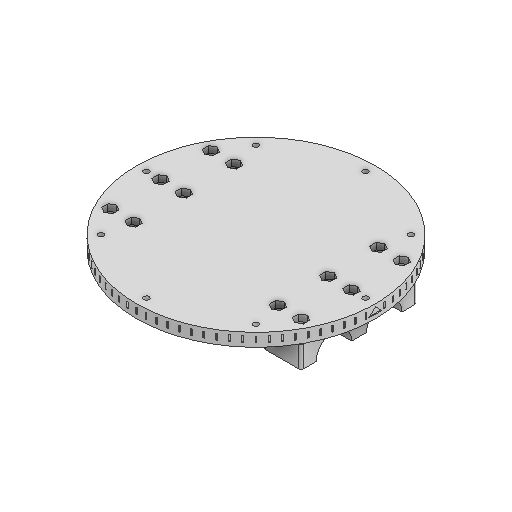
# Autodesk Inventor part: 3DP_PLA_A_Axis_Rotating_Stage_Fiberglass_pipes_mount_plate
Saved by Autodesk Inventor 2027 (Build 310192060, 192F)
## iProperties
Created: 2026-01-06
Part Number: 3DP_PLA_A_Axis_Rotating_Stage_Fiberglass_pipes_mount_plate
Material: Generic
Document SubType Name: Modeling
Designer: User
Density: 1 g/cm^3
Appearance: Default
Author: User
Autodesk Inventor part; units mm, degrees
ref_plane "XZ Plane" through (0, 0, 0) normal (0, 1, 0) x (-1, 0, 0)
ref_plane "XY Plane" through (0, 0, 0) normal (0, 0, 1) x (1, 0, 0)
sketch "Sketch1" plane through (0, 0, 0) normal (0, 1, 0) x (-1, 0, 0)
  circle A0 centre (0, 0) radius 92.675
  point P0 (85, 0)
  point P1 (60.1041, 60.1041)
  point P2 (0, 85)
  point P3 (-60.1041, 60.1041)
  point P4 (-85, 0)
  point P5 (-60.1041, -60.1041)
  point P6 (0, -85)
  point P7 (60.1041, -60.1041)
  dimension "d0" = 185.35
  dimension "d1" = 85
  dimension "d4" = 360
  constraints: 1 centre point, 1 coincident, 9 other
  measures "d0" diameter of A0
  measures "d1" distance of point (0, 0) point (85, 0)
extrude "Extrusion1" add sketch "Sketch1" along normal blind 10
hole "Hole1" at (-85, 0, 0) at (-60.1041, 0, 60.1041) at (0, 0, 85) at (60.1041, 0, 60.1041) at (85, 0, 0) at (60.1041, 0, -60.1041) at (0, 0, -85) at (-60.1041, 0, -60.1041) direction (0, 1, 0) diameter 4.2 end through all
sketch "Sketch3" plane through (0, 0, 0) normal (0, -1, 0) x (1, 0, 0)
  line L0 (-86.6006, 33) -> (86.6006, 33)
  line L1 (92.4806, 6) -> (-92.4806, 6)
  line L2 (-92.4806, -6) -> (92.4806, -6)
  line L3 (86.6006, -33) -> (-86.6006, -33)
  circle A0 centre (-60.1041, -60.1041) radius 2.1 projected
  circle A1 centre (0, -85) radius 2.1 projected
  circle A2 centre (60.1041, -60.1041) radius 2.1 projected
  circle A3 centre (85, 0) radius 2.1 projected
  circle A4 centre (60.1041, 60.1041) radius 2.1 projected
  circle A5 centre (0, 85) radius 2.1 projected
  circle A6 centre (-60.1041, 60.1041) radius 2.1 projected
  circle A7 centre (-85, 0) radius 2.1 projected
  circle A8 centre (0, 0) radius 92.675 projected
  line L4 (80, 45) -> (50, 45)
  line L5 (50, 45) -> (50, -45)
  line L6 (50, -45) -> (80, -45)
  line L7 (80, -45) -> (80, 45)
  line L8 (-50, 45) -> (-80, 45)
  line L9 (-80, 45) -> (-80, -45)
  line L10 (-80, -45) -> (-50, -45)
  line L11 (-50, -45) -> (-50, 45)
  line L12 (0, 85) -> (0, -85)
  point P0 (74, 39)
  point P1 (56, 39)
  point P2 (74, 0)
  point P3 (56, 0)
  point P4 (74, -39)
  point P5 (56, -39)
  point P6 (-74, 39)
  point P7 (-56, 39)
  point P8 (-74, 0)
  point P9 (-56, 0)
  point P10 (-74, -39)
  point P11 (-56, -39)
  dimension "d15" = 27
  dimension "d16" = 27
  dimension "d17" = 6
  dimension "d18" = 6
  dimension "d19" = 12
  dimension "d20" = 12
  dimension "d21" = 30
  dimension "d22" = 50
  dimension "d23" = 30
  dimension "d24" = 12
  dimension "d25" = 12
  dimension "d26" = 50
  dimension "d37" = 6
  dimension "d38" = 6
  dimension "d39" = 6
  dimension "d40" = 6
  dimension "d41" = 39
  dimension "d42" = 39
  dimension "d43" = 78
  constraints: 26 end point, 6 parallel, 6 symmetric about line, 4 horizontal, 4 vertical alignment, 2 horizontal alignment, 2 perpendicular, 1 vertical, 9 other
  measures "d15" distance between parallel lines of L0 L1
  measures "d16" distance between parallel lines of L3 L2
  measures "d17" distance from line of point (0, 0) L1
  measures "d18" distance from line of L2 point (0, 0)
  measures "d19" distance between parallel lines of L0 L4
  measures "d20" distance between parallel lines of L6 L3
  measures "d21" distance between parallel lines of L7 L5
  measures "d22" distance from line of point (0, 0) L5
  measures "d23" distance of L8.start L8.end
  measures "d24" distance between parallel lines of L0 L8
  measures "d25" distance between parallel lines of L3 L10
  measures "d26" distance from line of point (0, 0) L11
  measures "d37" distance from line of L4 point (56, 39)
  measures "d38" distance from line of L6 point (56, -39)
  measures "d39" distance from line of L5 point (56, 39)
  measures "d40" distance from line of L7 point (74, 39)
  measures "d41" distance of point (56, 0) point (56, 39)
  measures "d42" distance of point (74, 39) point (74, 0)
  measures "d43" distance of point (74, -39) point (74, 39)
extrude "Extrusion2" add sketch "Sketch3" along normal blind 18.5 contours L9 L8 L11 L0 | L0 L11 L1 L9 | L1 L11 L2 L9 | L7 L1 L5 L0 | L0 L5 L4 L7 | L2 L11 L3 L9 | L7 L2 L5 L1 | L3 L11 L10 L9 | L7 L3 L5 L2 | L7 L6 L5 L3
sketch "Sketch4" plane through (-80, 0, -45) normal (-1, 0, 0) x (0, 0, 1)
  line L0 (0, 0) -> (90, 0) projected
  line L1 (0, 0) -> (0, -18.5) projected
  line L2 (90, -18.5) -> (0, -18.5) projected
  line L3 (90, 0) -> (90, -18.5) projected
  circle A0 centre (64.5, -18.5) radius 13.75
  circle A1 centre (25.5, -18.5) radius 13.75
  line L4 (90, -18.5) -> (0, -18.5) projected
  point P0 (45, 0)
  point P1 (45, -18.5)
  point P2 (45, -18.5)
  dimension "d29" = 27.5
  dimension "d30" = 27.5
  dimension "d31" = 45
  dimension "d32" = 90
  dimension "d33" = 19.5
  dimension "d34" = 19.5
  constraints: 2 centre point, 2 midpoint, 2 point on line
  measures "d29" diameter of A0
  measures "d30" diameter of A1
  measures "d31" distance from line of L3 point (45, -18.5)
  measures "d32" distance between parallel lines of L1 L3
  measures "d33" distance of point (45, -18.5) A0.centre
  measures "d34" distance of point (45, -18.5) A1.centre
extrude "Extrusion3" cut sketch "Sketch4" against normal through all contours A1 L2 | L2 A1 | A0 L2 | L2 A0
hole "Hole2" at (74, 0, 39) at (56, 0, 39) at (74, 0, 0) at (56, 0, 0) at (74, 0, -39) at (56, 0, -39) at (-56, 0, 39) at (-56, 0, 0) at (-56, 0, -39) at (-74, 0, -39) at (-74, 0, 0) at (-74, 0, 39) direction (0, 1, 0) diameter 5.2 end through all both
fillet "Fillet1" radius 2 8 edges at (-80, -9.25, 45) (-50, -9.25, 45) (-80, -9.25, -45) (-50, -9.25, -45) (50, -9.25, 45) (80, -9.25, 45) (50, -9.25, -45) (80, -9.25, -45)
chamfer "Chamfer1" distance 2 angle 45 16 edges at (50, 0, 0) (50.5858, 0, 44.4142) (65, 0, 45) (79.4142, 0, 44.4142) (80, 0, 0) (79.4142, 0, -44.4142) (65, 0, -45) (50.5858, 0, -44.4142) (-65, 0, 45) (-50.5858, 0, 44.4142) (-50, 0, 0) (-50.5858, 0, -44.4142) (-65, 0, -45) (-79.4142, 0, -44.4142) (-80, 0, 0) (-79.4142, 0, 44.4142)
sketch "Sketch5" plane through (0, 10, 0) normal (0, 1, 0) x (1, 0, 0)
  circle A0 centre (-74, -39) radius 2.6 projected
  circle A1 centre (-74, 0) radius 2.6 projected
  circle A2 centre (-74, 39) radius 2.6 projected
  circle A3 centre (-56, 39) radius 2.6 projected
  circle A4 centre (-56, 0) radius 2.6 projected
  circle A5 centre (-56, -39) radius 2.6 projected
  circle A6 centre (56, 39) radius 2.6 projected
  circle A7 centre (74, 39) radius 2.6 projected
  circle A8 centre (56, 0) radius 2.6 projected
  circle A9 centre (74, 0) radius 2.6 projected
  circle A10 centre (56, -39) radius 2.6 projected
  circle A11 centre (74, -39) radius 2.6 projected
  circle A12 centre (-60.1041, 60.1041) radius 2.1 projected
  circle A13 centre (0, 85) radius 2.1 projected
  circle A14 centre (60.1041, 60.1041) radius 2.1 projected
  circle A15 centre (85, 0) radius 2.1 projected
  circle A16 centre (60.1041, -60.1041) radius 2.1 projected
  circle A17 centre (0, -85) radius 2.1 projected
  circle A18 centre (-60.1041, -60.1041) radius 2.1 projected
  circle A19 centre (-85, 0) radius 2.1 projected
  circle A20 centre (0, 0) radius 92.675 projected
  line L0 (-78.25, -36.5463) -> (-74, -34.0925)
  line L1 (-74, -34.0925) -> (-69.75, -36.5463)
  line L2 (-69.75, -36.5463) -> (-69.75, -41.4537)
  line L3 (-69.75, -41.4537) -> (-74, -43.9075)
  line L4 (-74, -43.9075) -> (-78.25, -41.4537)
  line L5 (-78.25, -41.4537) -> (-78.25, -36.5463)
  line L6 (-78.25, 2.4537) -> (-74, 4.9075)
  line L7 (-74, 4.9075) -> (-69.75, 2.4537)
  line L8 (-69.75, 2.4537) -> (-69.75, -2.4537)
  line L9 (-69.75, -2.4537) -> (-74, -4.9075)
  line L10 (-74, -4.9075) -> (-78.25, -2.4537)
  line L11 (-78.25, -2.4537) -> (-78.25, 2.4537)
  line L12 (-78.25, 41.4537) -> (-74, 43.9075)
  line L13 (-74, 43.9075) -> (-69.75, 41.4537)
  line L14 (-69.75, 41.4537) -> (-69.75, 36.5463)
  line L15 (-69.75, 36.5463) -> (-74, 34.0925)
  line L16 (-74, 34.0925) -> (-78.25, 36.5463)
  line L17 (-78.25, 36.5463) -> (-78.25, 41.4537)
  line L18 (-60.25, -36.5463) -> (-56, -34.0925)
  line L19 (-56, -34.0925) -> (-51.75, -36.5463)
  line L20 (-51.75, -36.5463) -> (-51.75, -41.4537)
  line L21 (-51.75, -41.4537) -> (-56, -43.9075)
  line L22 (-56, -43.9075) -> (-60.25, -41.4537)
  line L23 (-60.25, -41.4537) -> (-60.25, -36.5463)
  line L24 (-60.25, 2.4537) -> (-56, 4.9075)
  line L25 (-56, 4.9075) -> (-51.75, 2.4537)
  line L26 (-51.75, 2.4537) -> (-51.75, -2.4537)
  line L27 (-51.75, -2.4537) -> (-56, -4.9075)
  line L28 (-56, -4.9075) -> (-60.25, -2.4537)
  line L29 (-60.25, -2.4537) -> (-60.25, 2.4537)
  line L30 (-60.25, 41.4537) -> (-56, 43.9075)
  line L31 (-56, 43.9075) -> (-51.75, 41.4537)
  line L32 (-51.75, 41.4537) -> (-51.75, 36.5463)
  line L33 (-51.75, 36.5463) -> (-56, 34.0925)
  line L34 (-56, 34.0925) -> (-60.25, 36.5463)
  line L35 (-60.25, 36.5463) -> (-60.25, 41.4537)
  line L36 (0, -85) -> (0, 85)
  line L37 (78.25, -36.5463) -> (74, -34.0925)
  line L38 (74, -34.0925) -> (69.75, -36.5463)
  line L39 (69.75, -36.5463) -> (69.75, -41.4537)
  line L40 (69.75, -41.4537) -> (74, -43.9075)
  line L41 (74, -43.9075) -> (78.25, -41.4537)
  line L42 (78.25, -41.4537) -> (78.25, -36.5463)
  line L43 (78.25, 2.4537) -> (74, 4.9075)
  line L44 (74, 4.9075) -> (69.75, 2.4537)
  line L45 (69.75, 2.4537) -> (69.75, -2.4537)
  line L46 (69.75, -2.4537) -> (74, -4.9075)
  line L47 (74, -4.9075) -> (78.25, -2.4537)
  line L48 (78.25, -2.4537) -> (78.25, 2.4537)
  line L49 (78.25, 41.4537) -> (74, 43.9075)
  line L50 (74, 43.9075) -> (69.75, 41.4537)
  line L51 (69.75, 41.4537) -> (69.75, 36.5463)
  line L52 (69.75, 36.5463) -> (74, 34.0925)
  line L53 (74, 34.0925) -> (78.25, 36.5463)
  line L54 (78.25, 36.5463) -> (78.25, 41.4537)
  line L55 (60.25, -36.5463) -> (56, -34.0925)
  line L56 (56, -34.0925) -> (51.75, -36.5463)
  line L57 (51.75, -36.5463) -> (51.75, -41.4537)
  line L58 (51.75, -41.4537) -> (56, -43.9075)
  line L59 (56, -43.9075) -> (60.25, -41.4537)
  line L60 (60.25, -41.4537) -> (60.25, -36.5463)
  line L61 (60.25, 2.4537) -> (56, 4.9075)
  line L62 (56, 4.9075) -> (51.75, 2.4537)
  line L63 (51.75, 2.4537) -> (51.75, -2.4537)
  line L64 (51.75, -2.4537) -> (56, -4.9075)
  line L65 (56, -4.9075) -> (60.25, -2.4537)
  line L66 (60.25, -2.4537) -> (60.25, 2.4537)
  line L67 (60.25, 41.4537) -> (56, 43.9075)
  line L68 (56, 43.9075) -> (51.75, 41.4537)
  line L69 (51.75, 41.4537) -> (51.75, 36.5463)
  line L70 (51.75, 36.5463) -> (56, 34.0925)
  line L71 (56, 34.0925) -> (60.25, 36.5463)
  line L72 (60.25, 36.5463) -> (60.25, 41.4537)
  point P0 (-60.25, 39)
  point P1 (60.25, 39)
  dimension "d55" = 8.5
  dimension "d56" = 8.5
  dimension "d57" = 8.5
  dimension "d58" = 8.5
  dimension "d59" = 8.5
  dimension "d60" = 8.5
  constraints: 146 end point, 43 symmetric about line, 6 coincident, 5 equal length, 2 point on line, 1 midpoint, 1 vertical, 78 other
  measures "d55" distance between parallel lines of L2 L5
  measures "d56" distance between parallel lines of L11 L8
  measures "d57" distance between parallel lines of L17 L14
  measures "d58" distance between parallel lines of L20 L23
  measures "d59" distance between parallel lines of L26 L29
  measures "d60" distance between parallel lines of L32 L35
extrude "Extrusion4" cut sketch "Sketch5" against normal blind 5 contours A0 | A1 | A2 | A3 | A4 | A5 | A6 | A7 | A8 | A9 | A10 | A11 | L0 L1 L2 L3 L4 L5 | L6 L7 L8 L9 L10 L11 | L12 L13 L14 L15 L16 L17 | L18 L19 L20 L21 L22 L23 | L24 L25 L26 L27 L28 L29 | L30 L31 L32 L33 L34 L35 | L42 L41 L40 L39 L38 L37 | L48 L47 L46 L45 L44 L43 | L54 L53 L52 L51 L50 L49 | L60 L59 L58 L57 L56 L55 | L66 L65 L64 L63 L62 L61 | L72 L71 L70 L69 L68 L67
sketch "Sketch6" plane through (0, 0, 0) normal (0, -1, 0) x (1, 0, 0)
  circle A0 centre (-85, 0) radius 2.1 projected
  circle A1 centre (85, 0) radius 2.1 projected
  line L0 (80, -5.75) -> (80, 5.75) projected
  line L1 (-80, 5.75) -> (-80, -5.75) projected
  circle A2 centre (-85, 0) radius 5
  circle A3 centre (85, 0) radius 5
  point P0 (0, 0)
  constraints: 2 centre point, 2 coincident
extrude "Extrusion5" cut sketch "Sketch6" along normal blind 5
ref_plane "Work Plane1" through (92.675, 0, 0) normal (1, 0, 0) x (0, 1, 0)
sketch "Sketch8" plane through (92.675, 0, 0) normal (1, 0, 0) x (0, 1, 0)
  line L0 (3, -5) -> (3, 5)
  line L1 (3, 5) -> (8, 0)
  line L2 (3, -5) -> (8, 0)
  line L3 (3, -5) -> (13.0915, -5) construction
  line L4 (0, -43.1903) -> (0, 43.1903) projected
  point P0 (0, 0)
  point P1 (0, 0)
  dimension "d65" = 10
  dimension "d67" = 45
  dimension "d69" = 45
  dimension "d70" = 5
  dimension "d71" = 3
  constraints: 8 end point, 1 horizontal, 1 midpoint, 1 vertical
  measures "d65" distance of L0.start L0.end
  measures "d67" angle of L0 L1
  measures "d69" angle of L3 L2
  measures "d70" vertical distance of point (0, 0) L0.start
  measures "d71" distance between parallel lines of L4 L0
extrude "Extrusion6" cut sketch "Sketch8" against normal blind 0.6
sketch "Sketch9" plane through (92.675, 0, 0) normal (1, 0, 0) x (0, 1, 0)
  line L0 (3, 5) -> (3, -5) projected
  line L1 (3, -5) -> (8, 0) projected
  line L2 (8, 0) -> (3, 5) projected
  line L3 (3, -0.5) -> (7.5, -0.5)
  line L4 (7.5, -0.5) -> (7.5, 0.5)
  line L5 (7.5, 0.5) -> (3, 0.5)
  line L6 (3, 0.5) -> (3, -0.5)
  line L7 (0, -43.1903) -> (0, 43.1903) projected
  point P0 (0, 0)
  point P1 (0, 0)
  dimension "d74" = 1
  dimension "d75" = 4.5
  dimension "d76" = 0.5
  constraints: 8 end point, 2 parallel, 2 point on line, 1 horizontal, 1 midpoint, 1 perpendicular
  measures "d74" distance between parallel lines of L5 L3
  measures "d75" distance between parallel lines of L0 L4
  measures "d76" distance from line of point (0, 0) L3
extrude "Extrusion7" cut sketch "Sketch9" against normal blind 0.8 contours L5 L4 L3 L0
pattern_circular "Circular Pattern1" count 80 over 360 about axis through (0, 0, 0) along (0, 1, 0) of "Extrusion7"
sketch "Sketch10" plane through (92.075, 0, 0) normal (1, 0, 0) x (0, 0, -1)
  line L0 (0.5, 7.5) -> (0.5, 3) projected
  line L1 (5, 3) -> (0.5, 3) projected
  line L2 (0.5, 7.5) -> (5, 3) projected
  line L3 (-0.5, 3) -> (-0.5, 7.5) projected
  line L4 (-5, 3) -> (-0.5, 7.5) projected
  line L5 (-0.5, 3) -> (-5, 3) projected
  line L6 (-0.5, 7.5) -> (0.5, 7.5) projected
  line L7 (0, 8) -> (0.5, 7.5) projected
  line L8 (-0.5, 7.5) -> (0, 8) projected
  point P0 (0, 0)
extrude "Extrusion8" cut sketch "Sketch10" against normal up to surface (0.2 mm away)
equation "\"d18\" = d17"
equation "\"d20\" = d19"
equation "\"d23\" = d21"
equation "\"d26\" = d22"
equation "\"d40\" = d39"
equation "\"d41\" = d42"
equation "\"d42\" = 0.5 * d43"
equation "\"d34\" = d33"
equation "\"d56\" = d55"
equation "\"d57\" = d56"
equation "\"d58\" = d55"
equation "\"d59\" = d55"
equation "\"d60\" = d55"
equation "\"d70\" = 0.5 * d65"
body "Solid1"
